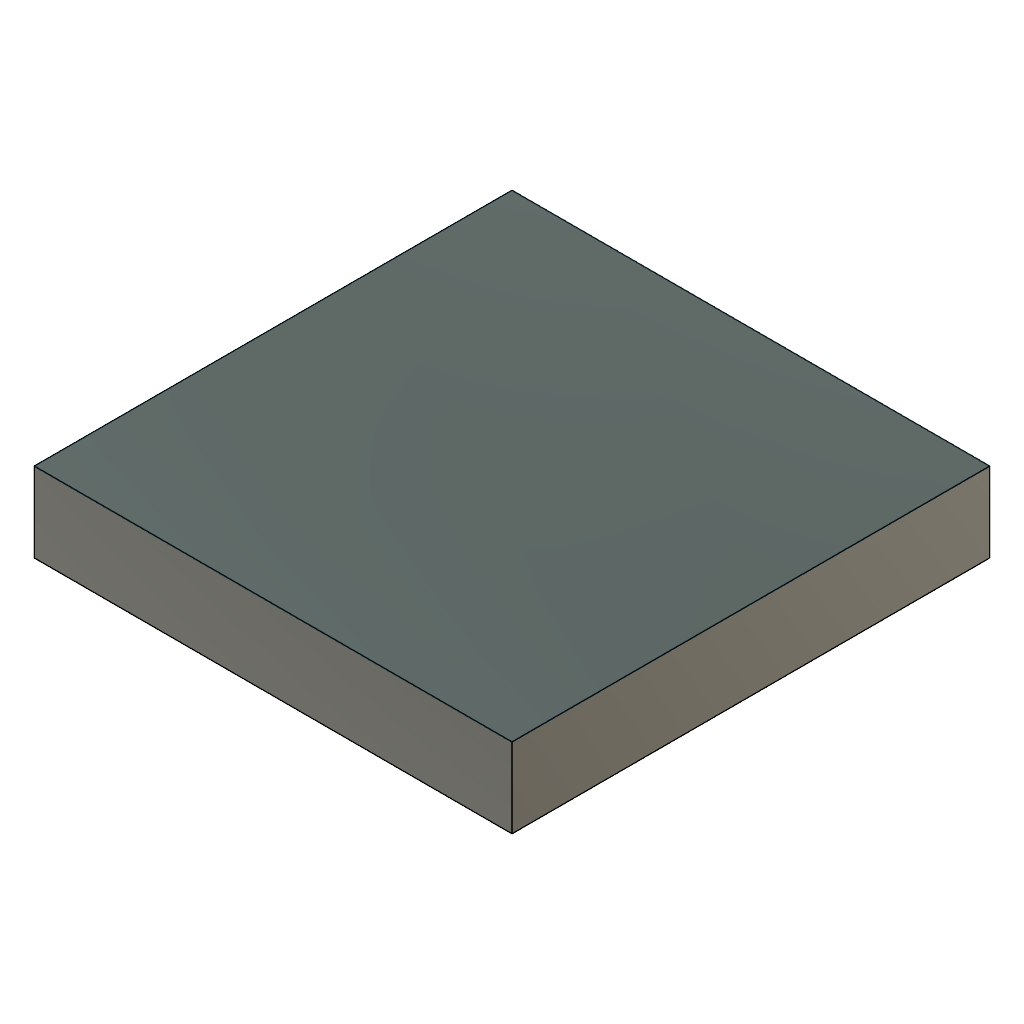
HotPlateFusionMesh (Autodesk Fusion 360 design; units mm, degrees)
part number: 2026-10-25-13-26-59-914
Autodesk Fusion 360 part; units mm, degrees
sketch "Sketch1" plane through (0, 0, 0) normal (0, 0, 1) x (1, 0, 0)
  line L0 (0, 0) -> (150, 0)
  line L1 (150, 0) -> (150, 150)
  line L2 (150, 150) -> (0, 150)
  line L3 (0, 150) -> (0, 0)
  dimension "d1" = 150
  dimension "d2" = 150
  constraint horizontal L0
  constraint vertical L1
  constraint horizontal L2
  constraint vertical L3
  constraint coincident L0.start L3.end
  measures "d1" distance of L0.start L0.end
  measures "d2" distance of L0.start L2.end
extrude "Extrude1" add sketch "Sketch1" along normal blind 25
sketch "Sketch2" plane through (0, 0, 25) normal (0, 0, 1) x (-1, 0, 0)
  line L0 (0, -150) -> (0, 0)
  line L1 (0, 0) -> (-150, 0)
  line L2 (-150, 0) -> (-150, -150)
  line L3 (-150, -150) -> (0, -150)
sketch "Sketch3" plane through (0, 0, 0) normal (0, 0, -1) x (1, 0, 0)
  line L0 (0, 0) -> (0, -150)
  line L1 (0, -150) -> (150, -150)
  line L2 (150, -150) -> (150, 0)
  line L3 (150, 0) -> (0, 0)
  circle A0 centre (50.2286, -50) radius 3.125
  circle A1 centre (75, -50) radius 3.125
  circle A2 centre (125, -50) radius 3.125
  circle A3 centre (25, -50) radius 3.125
  circle A4 centre (100, -50) radius 3.125
  circle A5 centre (50.2286, -75) radius 3.125
  circle A6 centre (75, -75) radius 3.125
  circle A7 centre (125, -75) radius 3.125
  circle A8 centre (25, -75) radius 3.125
  circle A9 centre (100, -75) radius 3.125
  circle A10 centre (50.2286, -100) radius 3.125
  circle A11 centre (75, -100) radius 3.125
  circle A12 centre (125, -100) radius 3.125
  circle A13 centre (25, -100) radius 3.125
  circle A14 centre (100, -100) radius 3.125
  circle A15 centre (50.2286, -125) radius 3.125
  circle A16 centre (75, -125) radius 3.125
  circle A17 centre (125, -125) radius 3.125
  circle A18 centre (25, -125) radius 3.125
  circle A19 centre (100, -125) radius 3.125
  circle A20 centre (25.7153, -30.3214) radius 3.125
  circle A21 centre (50, -30) radius 3.125
  circle A22 centre (75.0819, -30.0746) radius 3.125
  circle A23 centre (100, -30) radius 3.125
  circle A24 centre (125.4359, -30.3214) radius 3.125
  point P0 (25, -50)
  point P1 (25, -50)
  point P2 (25, -75)
  point P3 (25, -75)
  point P4 (25, -100)
  point P5 (25, -100)
  point P6 (25, -125)
  point P7 (25, -125)
  dimension "d10" = 6.25
  dimension "d11" = 6.25
  dimension "d12" = 6.25
  dimension "d13" = 6.25
  dimension "d14" = 6.25
  dimension "d15" = 6.25
  dimension "d16" = 6.25
  dimension "d17" = 6.25
  dimension "d18" = 6.25
  dimension "d19" = 6.25
  dimension "d20" = 6.25
  dimension "d21" = 6.25
  dimension "d22" = 6.25
  dimension "d23" = 6.25
  dimension "d24" = 6.25
  dimension "d25" = 6.25
  dimension "d26" = 6.25
  dimension "d27" = 6.25
  dimension "d28" = 6.25
  dimension "d29" = 6.25
  dimension "d32" = 6.25
  dimension "d33" = 6.25
  dimension "d34" = 6.25
  dimension "d35" = 6.25
  dimension "d36" = 6.25
  constraint coincident P1 P0
  constraint coincident P3 P2
  constraint coincident P5 P4
  constraint coincident P7 P6
  measures "d10" diameter of A3
  measures "d11" diameter of A0
  measures "d12" diameter of A1
  measures "d13" diameter of A4
  measures "d14" diameter of A2
  measures "d15" diameter of A8
  measures "d16" diameter of A5
  measures "d17" diameter of A6
  measures "d18" diameter of A9
  measures "d19" diameter of A7
  measures "d20" diameter of A13
  measures "d21" diameter of A10
  measures "d22" diameter of A11
  measures "d23" diameter of A14
  measures "d24" diameter of A12
  measures "d25" diameter of A18
  measures "d26" diameter of A15
  measures "d27" diameter of A16
  measures "d28" diameter of A19
  measures "d29" diameter of A17
  measures "d32" diameter of A20
  measures "d33" diameter of A21
  measures "d34" diameter of A22
  measures "d35" diameter of A23
  measures "d36" diameter of A24
extrude "Extrude2" cut sketch "Sketch3" against normal blind 13 contours A0 | A1 | A2 | A3 | A4 | A5 | A6 | A7 | A8 | A9 | A10 | A11 | A12 | A13 | A14 | A15 | A16 | A17 | A18 | A19 | A20 | A21 | A22 | A23 | A24
